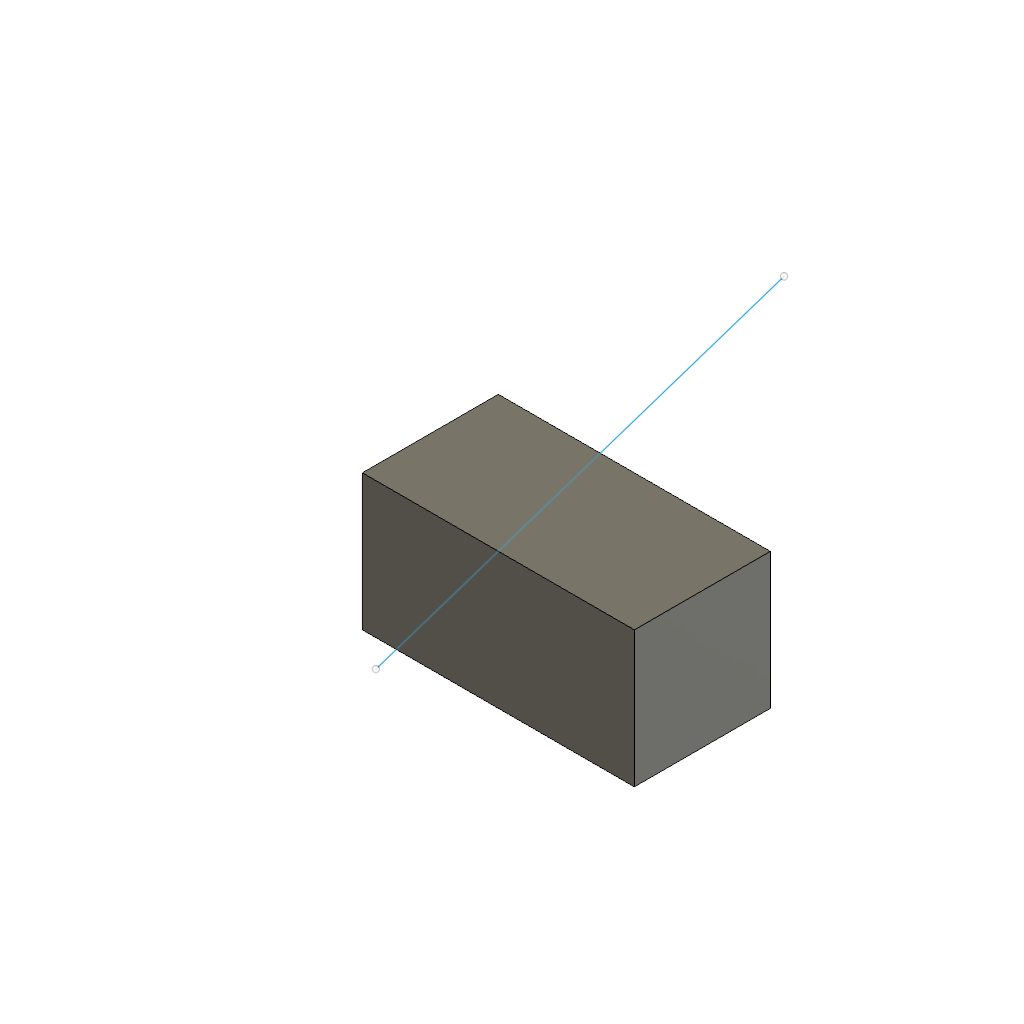
along_sketch_line (Autodesk Fusion 360 design; units mm, degrees)
part number: 2026-10-20-21-11-18-024
Autodesk Fusion 360 part; units mm, degrees
sketch "Sketch1" plane through (0, 0, 0) normal (0, 0, 1) x (1, 0, 0)
  line L0 (0, 0) -> (20, 0)
  line L1 (20, 0) -> (20, 10)
  line L2 (20, 10) -> (0, 10)
  line L3 (0, 10) -> (0, 0)
extrude "Extrude1" add sketch "Sketch1" along normal blind 10
sketch "MoveDirection" plane through (0, 0, 0) normal (0, 0, 1) x (1, 0, 0)
  line L0 (0, 0) -> (30, 40)
move_body "ProbeMove" bodies 1 to x (1, 0, 0) y (0, 1, 0) z (0, 0, 1) at (9, 12, 0)
named bodies: "MovedBody"
